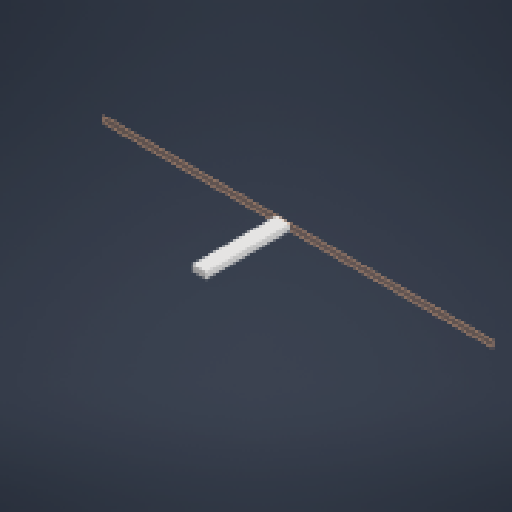
# Autodesk Inventor part: 2x4x21
Saved by Autodesk Inventor 2027 (Build 310192000, 192)
## iProperties
Created: 2026-10-18
Part Number: 2x4x21
Material: Generic
Document SubType Name: Modeling
Designer: lucas
Density: 1 g/cm^3
Appearance: Default
Author: lucas
Autodesk Inventor part; units mm, degrees
ref_plane "YZ Plane" through (0, 0, 0) normal (1, 0, 0) x (0, 1, 0)
ref_plane "XZ Plane" through (0, 0, 0) normal (0, 1, 0) x (-1, 0, 0)
ref_plane "XY Plane" through (0, 0, 0) normal (0, 0, 1) x (1, 0, 0)
ref_plane "Work Plane1" through (0, 0, 0) normal (0, 0, 1) x (1, 0, 0)
sketch "Sketch1" plane through (0, 0, 0) normal (0, 0, 1) x (1, 0, 0)
  line L0 (0, 0) -> (2235.2, 0) projected
  line L1 (2235.2, 0) -> (2235.2, 38.1) projected
  line L2 (0, 38.1) -> (2235.2, 38.1) projected
  line L3 (0, 0) -> (0, 38.1) projected
  line L4 (0, 0) -> (2235.2, 0) projected
  line L5 (2235.2, 0) -> (2235.2, 38.1) projected
  line L6 (0, 38.1) -> (2235.2, 38.1) projected
  line L7 (0, 0) -> (0, 38.1) projected
  line L8 (0, 0) -> (2235.2, 0) projected
  line L9 (2235.2, 0) -> (2235.2, 38.1) projected
  line L10 (0, 38.1) -> (2235.2, 38.1) projected
  line L11 (0, 0) -> (0, 38.1) projected
  line L12 (0, 38.1) -> (2235.2, 38.1) projected
  line L13 (0, 38.1) -> (2235.2, 38.1) projected
  line L14 (0, 0) -> (2235.2, 0) projected
  line L15 (1371.6, 38.1) -> (1460.5, 38.1)
  line L16 (1460.5, 38.1) -> (1460.5, 0)
  line L17 (1460.5, 0) -> (1371.6, 0)
  line L18 (1371.6, 0) -> (1371.6, 38.1)
  point P0 (1371.6, 38.1)
  point P1 (1371.6, 0)
  point P2 (1460.5, 0)
  point P3 (1460.5, 38.1)
  dimension "d0" = 88.9
  constraints: 8 end point, 2 parallel, 2 point on line, 1 horizontal, 1 perpendicular
  measures "d0" distance between parallel lines of L16 L18
extrude "Extrusion1" add sketch "Sketch1" along normal blind 533.4 contours L18 L2 L16 L0
body "Solid1"
